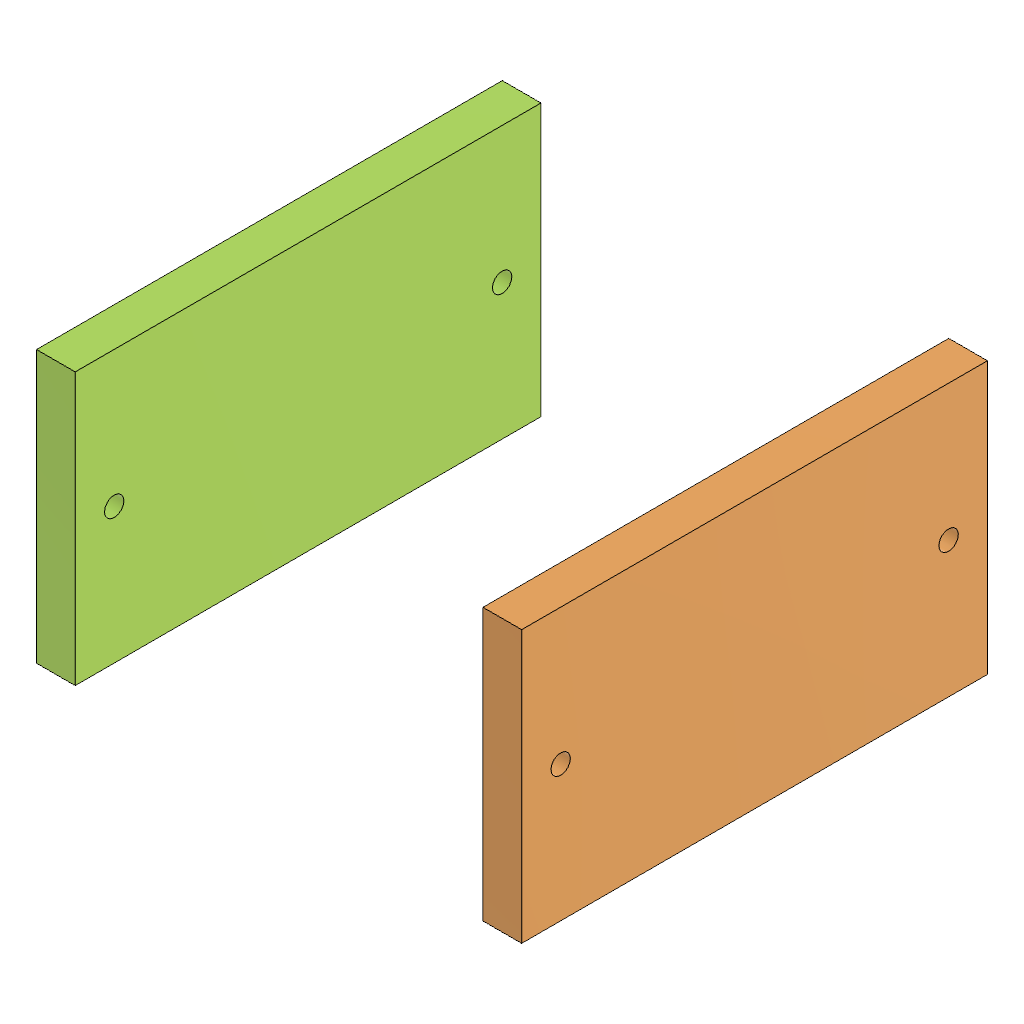
body+2 (Autodesk Fusion 360 design; units mm, degrees)
part number: 2026-10-02-22-04-13-816
part number: 2026-10-02-22-08-31-767
part number: 2026-10-03-21-46-52-269
Autodesk Fusion 360 part; units mm, degrees
sketch "Sketch1" plane through (0, 0, 0) normal (1, 0, 0) x (0, 1, 0)
  line L0 (60, 35) -> (-60, 35)
  line L1 (-60, 35) -> (-60, -35)
  line L2 (-60, -35) -> (60, -35)
  line L3 (60, -35) -> (60, 35)
  line L4 (60, 35) -> (-60, -35) construction
  line L5 (-60, 35) -> (60, -35) construction
  circle A0 centre (-49.9622, 0) radius 2.5
  circle A1 centre (49.9622, 0) radius 2.5
  dimension "d1" = 120
  dimension "d2" = 70
  dimension "d3" = 5
  constraint horizontal L0
  constraint perpendicular L0 L1
  constraint parallel L0 L2
  constraint parallel L1 L3
  constraint coincident L4 origin
  constraint coincident L5 origin
  measures "d1" distance of L1.end L2.end
  measures "d2" distance of L0.end L1.end
  measures "d3" diameter of A0
extrude "Extrude1" add sketch "Sketch1" along normal blind 10 makes body 1
copy_body "Body->Comp1" bodies 1 removing the originals makes body 2 in component "Component"
copy_body "CopyPasteBodies1" bodies 2 makes body 3
move_body "Move1" bodies 3 to x (1, 0, 0) y (0, 1, 0) z (0, 0, 1) at (115, 0, 0)
copy_body "Body->Comp2" bodies 3 removing the originals makes body 4 in component "Component'"
component "Component" placed x (1, 0, 0) y (0, 1, 0) z (0, 0, 1) at (0, 0, 0)
component "Component'" placed x (1, 0, 0) y (0, 1, 0) z (0, 0, 1) at (0, 0, 0)
